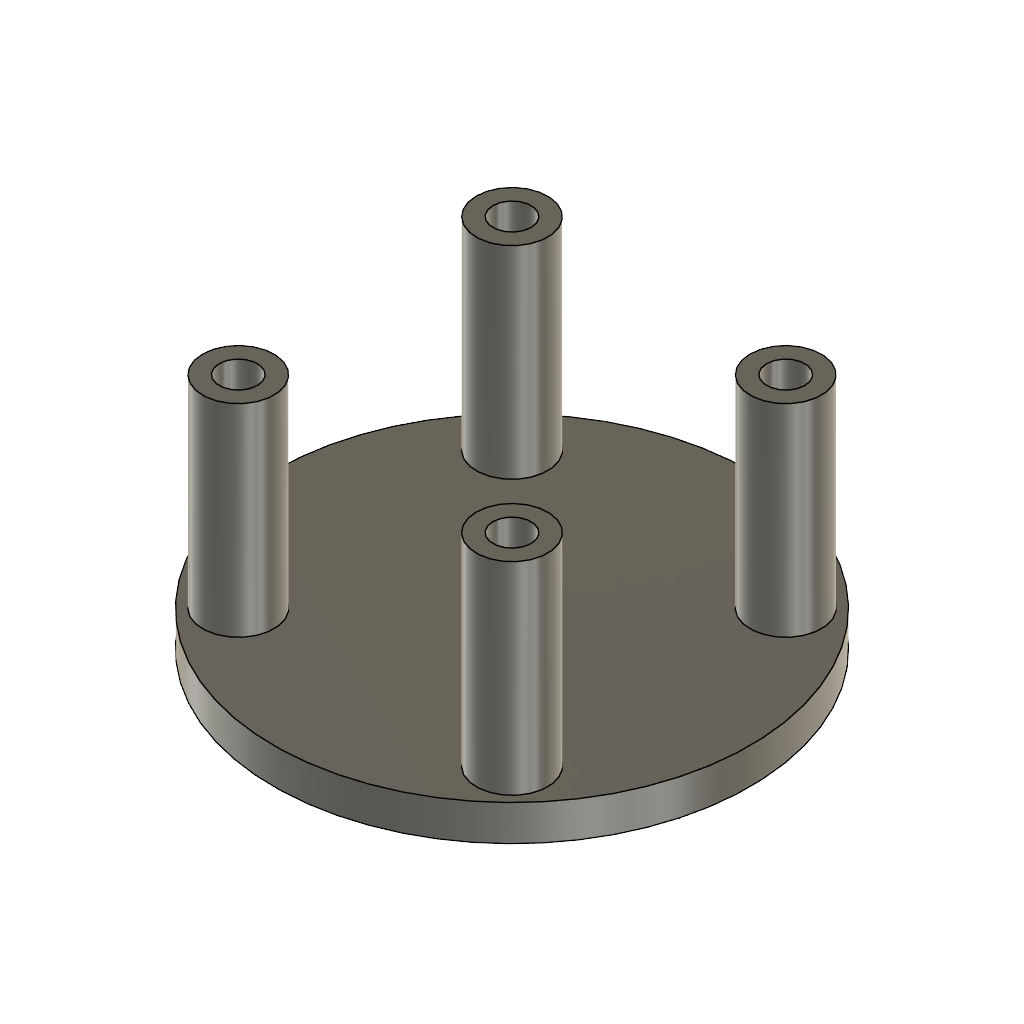
02-31 Humidity inlet cap (Autodesk Fusion 360 design; units mm, degrees)
Autodesk Fusion 360 part; units mm, degrees
sketch "Sketch1" plane through (0, 0, 0) normal (0, 0, 1) x (1, 0, 0)
  circle A0 centre (-11.5, 11.5) radius 3
  circle A1 centre (11.5, 11.5) radius 3
  circle A2 centre (11.5, -11.5) radius 3
  circle A3 centre (-11.5, -11.5) radius 3
  dimension "d1" = 11.5
  dimension "d2" = 11.5
  dimension "d3" = 6
  dimension "d4" = 23
  dimension "d5" = 23
  constraint horizontal A0.centre A1.centre
  constraint vertical A0.centre A3.centre
  constraint horizontal A2.centre A3.centre
  constraint vertical A1.centre A2.centre
  constraint equal A0 A3
  constraint equal A2 A3
  constraint equal A1 A2
  measures "d1" vertical distance of origin A0.centre
  measures "d2" horizontal distance of origin A0.centre
  measures "d3" diameter of A0
  measures "d4" distance of A0.centre A3.centre
  measures "d5" distance of A0.centre A1.centre
extrude "Extrude1" add sketch "Sketch1" along normal blind 20 makes body 1 at (-8.5037, 11.3505, 13.3333) makes body 2 at (-8.5037, -11.6495, 13.3333) makes body 3 at (14.4963, 11.3505, 13.3333) makes body 4 at (14.4963, -11.6495, 13.3333)
sketch "Sketch2" plane through (0, 0, 0) normal (0, 0, 1) x (1, 0, 0)
  circle A0 centre (0, 0) radius 20
  constraint coincident A0.centre origin
extrude "Extrude2" add sketch "Sketch2" along normal blind 3 bodies 1 2 3 4
sketch "Sketch3" plane through (0, 0, 20) normal (0, 0, 1) x (-1, 0, 0)
  circle A0 centre (11.5, -11.5) radius 3
  circle A1 centre (11.5, -11.5) radius 1.6
  circle A2 centre (11.5, 11.5) radius 1.6
  circle A3 centre (-11.5, 11.5) radius 1.6
  circle A4 centre (-11.5, -11.5) radius 1.6
  circle A5 centre (-11.5, -11.5) radius 3
  circle A6 centre (-11.5, 11.5) radius 3
  circle A7 centre (11.5, 11.5) radius 3
  dimension "d11" = 3.2
  constraint concentric A0 A1
  constraint concentric A4 A5
  constraint concentric A3 A6
  constraint concentric A2 A7
  constraint equal A1 A2
  constraint equal A2 A3
  constraint equal A3 A4
  measures "d11" diameter of A1
extrude "Extrude3" cut sketch "Sketch3" against normal blind 36 contours A1 | A2 | A3 | A4 bodies 1
